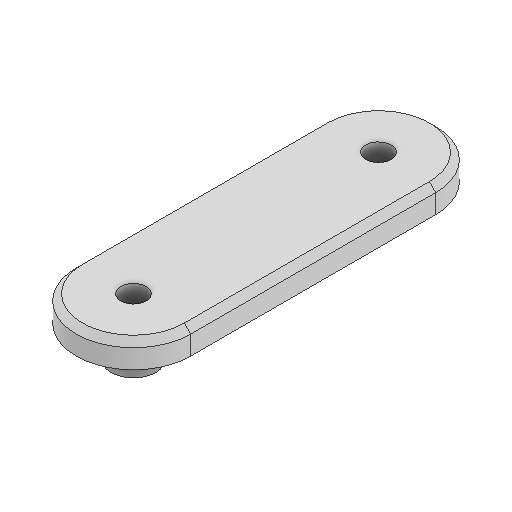
# Autodesk Inventor part: 3DP_PLA_A_Axis_Idler_Stiffening_Bracket
Saved by Autodesk Inventor 2027 (Build 310192060, 192F)
## iProperties
Created: 2026-01-18
Part Number: 3DP_PLA_A_Axis_Idler_Stiffening_Bracket
Material: Generic
Document SubType Name: Modeling
Designer: Andrzej
Density: 1 g/cm^3
Appearance: Default
Author: Andrzej
Autodesk Inventor part; units mm, degrees
ref_plane "YZ Plane" through (0, 0, 0) normal (1, 0, 0) x (0, 1, 0)
ref_plane "XZ Plane" through (0, 0, 0) normal (0, 1, 0) x (-1, 0, 0)
ref_plane "XY Plane" through (0, 0, 0) normal (0, 0, 1) x (1, 0, 0)
sketch "Sketch1" plane through (0, 0, 0) normal (0, 1, 0) x (-1, 0, 0)
  arc A0 (9, 19.275) -> (-9, 19.275) centre (0, 19.275) ccw
  arc A1 (-9, -19.275) -> (9, -19.275) centre (0, -19.275) ccw
  line L0 (9, 19.275) -> (9, -19.275)
  line L1 (-9, 19.275) -> (-9, -19.275)
  circle A2 centre (0, 19.275) radius 3.5
  circle A3 centre (0, 19.275) radius 2
  circle A4 centre (0, -19.275) radius 3.5
  circle A5 centre (0, -19.275) radius 2
  point P0 (0, 0)
  dimension "d0" = 18
  dimension "d1" = 18
  dimension "d2" = 38.55
  dimension "d3" = 19.275
  dimension "d4" = 7
  dimension "d5" = 4
  dimension "d6" = 7
  dimension "d7" = 4
  constraints: 6 centre point, 4 coincident, 4 end point, 4 point on circle, 2 tangent
  measures "d0" diameter of A0
  measures "d1" diameter of A1
  measures "d2" distance of A1.centre A0.centre
  measures "d3" distance of point (0, 0) A0.centre
  measures "d4" diameter of A2
  measures "d5" diameter of A3
  measures "d6" diameter of A4
  measures "d7" diameter of A5
extrude "Extrusion1" add sketch "Sketch1" along normal blind 4 contours L0 A1 L1 A0 | A2 | A4
chamfer "Chamfer1" distance 1 angle 45 4 edges at (0, 4, 28.275) (9, 4, 0) (0, 4, -28.275) (-9, 4, 0)
extrude "Extrusion2" add sketch "Sketch1" against normal blind 5 contours A2 | A4
equation "\"d3\" = 0.5 * d2"
body "Solid1"
